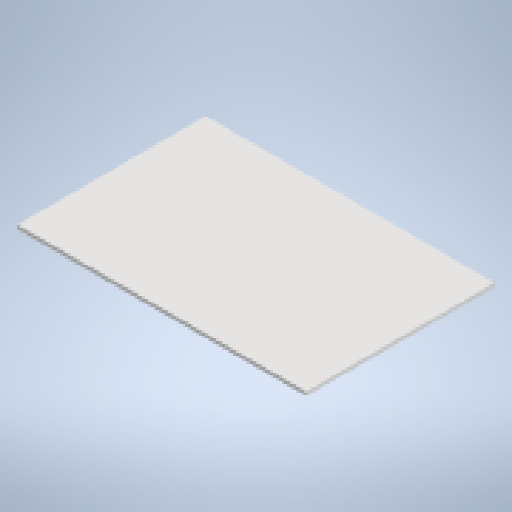
# Autodesk Inventor part: низ
Saved by Autodesk Inventor 2024.2 (Build 282272000, 272)
## iProperties
Created: 2026-10-08
Part Number: низ
Material: Типовые
Document SubType Name: Modeling
Designer: User
Density: 1 g/cm^3
Appearance: По умолчанию
Author: User
Autodesk Inventor part; units mm, degrees
ref_plane "YZ Plane" through (0, 0, 0) normal (1, 0, 0) x (0, 1, 0)
ref_plane "XZ Plane" through (0, 0, 0) normal (0, 1, 0) x (-1, 0, 0)
ref_plane "XY Plane" through (0, 0, 0) normal (0, 0, 1) x (1, 0, 0)
sketch "Эскиз1" plane through (0, 0, 0) normal (0, 1, 0) x (-1, 0, 0)
  line L0 (-254.1394, -150) -> (205.8606, -150)
  line L1 (205.8606, -150) -> (205.8606, 150)
  line L2 (205.8606, 150) -> (-254.1394, 150)
  line L3 (-254.1394, 150) -> (-254.1394, -150)
  line L4 (225.8606, -152.141) -> (225.8606, 197.859) projected
  line L5 (-274.1394, 197.859) -> (-274.1394, -152.141) projected
  point P0 (0, 0)
  dimension "d0" = 460
  dimension "d1" = 300
  dimension "d4" = 20
  constraints: 8 end point, 2 parallel, 1 horizontal, 1 perpendicular
  measures "d0" distance of L1.end L2.end
  measures "d1" distance of L0.end L1.end
  measures "d4" distance between parallel lines of L1 L4
extrude "Выдавливание1" add sketch "Эскиз1" along normal blind 6
